VarriableCase (Autodesk Fusion 360 design; units mm, degrees)
Autodesk Fusion 360 part; units mm, degrees
sketch "Sketch1" plane through (0, 0, 0) normal (0, 1, 0) x (1, 0, 0)
  line L0 (140, -74.5) -> (-140, -74.5)
  line L1 (-140, -74.5) -> (-140, 75.5)
  line L2 (-140, 75.5) -> (140, 75.5)
  line L3 (140, 75.5) -> (140, -74.5)
  line L4 (150, -84.5) -> (-150, -84.5)
  line L5 (-150, -84.5) -> (-150, 84.5)
  line L6 (-150, 84.5) -> (150, 84.5)
  line L7 (150, 84.5) -> (150, -84.5)
  line L8 (150, 11.3529) -> (212.0868, 7.5031)
  line L9 (135.5, 63) -> (135.5, -62)
  line L10 (135.5, -62) -> (10.5, -62)
  line L11 (10.5, -62) -> (-9.5, -62)
  line L12 (-9.5, -62) -> (-134.5, -62)
  line L13 (-134.5, -62) -> (-134.5, 63)
  line L14 (-134.5, 63) -> (-9.5, 63)
  line L15 (-9.5, 63) -> (10.5, 63)
  line L16 (10.5, 63) -> (135.5, 63)
  circle A0 centre (-134.5, 63) radius 1.25
  circle A1 centre (-134.5, -62) radius 1.25
  circle A2 centre (-9.5, -62) radius 1.25
  circle A3 centre (-9.5, 63) radius 1.25
  circle A4 centre (10.5, 63) radius 1.25
  circle A5 centre (135.5, 63) radius 1.25
  circle A6 centre (135.5, -62) radius 1.25
  circle A7 centre (-9.5, -62) radius 5
  circle A8 centre (135.5, -62) radius 5
  circle A9 centre (135.5, 63) radius 5
  circle A10 centre (10.5, 63) radius 5
  circle A11 centre (-9.5, 63) radius 5
  circle A12 centre (-134.5, 63) radius 5
  circle A13 centre (-134.5, -62) radius 5
  line L17 (10.5, 63) -> (10.5, -62) construction
  circle A14 centre (10.5, -62) radius 1.25
  circle A15 centre (10.5, -62) radius 5
  dimension "d14" = 2.5
  dimension "d15" = 2.5
  dimension "d16" = 2.5
  dimension "d17" = 2.5
  dimension "d18" = 2.5
  dimension "d19" = 2.5
  dimension "d20" = 2.5
  dimension "d21" = 10
  dimension "d22" = 10
  dimension "d23" = 10
  dimension "d24" = 10
  dimension "d25" = 10
  dimension "d26" = 10
  dimension "d27" = 10
  dimension "d42" = 2.5
  dimension "d43" = 10
  constraint perpendicular L0 L1
  constraint parallel L0 L2
  constraint parallel L1 L3
  constraint horizontal L0
  constraint perpendicular L4 L5
  constraint parallel L4 L6
  constraint parallel L5 L7
  constraint horizontal L4
  constraint coincident L7 L8.start
  constraint perpendicular L9 L10
  constraint parallel L10 L11
  constraint parallel L11 L12
  constraint perpendicular L12 L13
  constraint perpendicular L13 L14
  constraint parallel L14 L15
  constraint perpendicular L9 L16
  constraint coincident L13.end L14.start
  constraint coincident L12.end L13.start
  constraint coincident L11.end L12.start
  constraint coincident L14.end L15.start
  constraint coincident L15.end L16.start
  constraint coincident L9.start L16.end
  constraint coincident L9.end L10.start
  constraint concentric A6 A8
  constraint concentric A5 A9
  constraint concentric A4 A10
  constraint concentric A3 A11
  constraint concentric A0 A12
  constraint concentric A1 A13
  constraint perpendicular L11 L17
  constraint coincident L10.end L11.start
  constraint concentric A14 A15
  measures "d14" diameter of A0
  measures "d15" diameter of A1
  measures "d16" diameter of A2
  measures "d17" diameter of A3
  measures "d18" diameter of A4
  measures "d19" diameter of A5
  measures "d20" diameter of A6
  measures "d21" diameter of A7
  measures "d22" diameter of A8
  measures "d23" diameter of A9
  measures "d24" diameter of A10
  measures "d25" diameter of A11
  measures "d26" diameter of A12
  measures "d27" diameter of A13
  measures "d42" diameter of A14
  measures "d43" diameter of A15
extrude "Extrude1" add sketch "Sketch1" along normal blind 14.28 contours L0 L1 L2 L3 L10 L11 L12 L13 L14 L15 L16 A7 A8 A9 A10 A11 A12 A13 A15 | L3 L9 L10 A6 A8 | L3 A8 | L3 L9 A8 A9 | L9 L10 A6 A8 | L3 L9 L16 A5 A9 | L3 A9 | L10 L11 A14 A15 | L10 L11 A14 A15 | L9 L16 A5 A9 | L11 L12 A2 A7 | L11 L12 A2 A7 | L15 L16 A4 A10 | L15 L16 A4 A10 | L12 L13 A1 A13 | L12 L13 A1 A13 | L14 L15 A3 A11 | L14 L15 A3 A11 | L13 L14 A0 A12 | L13 L14 A0 A12 | L4 L5 L6 L7
chamfer "Chamfer1" distance 5 angle 45 8 edges at (-14.5, 7.14, -63) (-4.5, 7.14, -63) (5.5, 7.14, -63) (15.5, 7.14, -63) (-4.5, 7.14, 62) (-14.5, 7.14, 62) (5.5, 7.14, 62) (15.5, 7.14, 62) tangent chain off
chamfer "Chamfer2" distance 3 angle 45 8 edges at (-129.5, 7.14, -63) (-134.5, 7.14, -58) (-134.5, 7.14, 57) (-129.5, 7.14, 62) (130.5, 7.14, 62) (135.5, 7.14, 57) (135.5, 7.14, -58) (130.5, 7.14, -63) tangent chain off
sketch "Sketch2" plane through (0, 14.28, 0) normal (0, 1, 0) x (-1, 0, 0)
  circle A0 centre (9.5, -63) radius 1.25
  circle A1 centre (134.5, 62) radius 1.25
  circle A2 centre (134.5, -63) radius 1.25
  line L0 (19.5, 62) -> (126.5, 62)
  line L1 (126.5, 62) -> (130.4, 59.1382)
  arc A3 (130.4, 59.1382) -> (131.6382, 57.9) centre (134.5, 62) ccw
  line L2 (131.6382, 57.9) -> (134.5, 54)
  line L3 (134.5, 54) -> (134.5, -55)
  line L4 (134.5, -55) -> (131.6382, -58.9)
  arc A4 (131.6382, -58.9) -> (130.4, -60.1382) centre (134.5, -63) ccw
  line L5 (130.4, -60.1382) -> (126.5, -63)
  line L6 (126.5, -63) -> (19.5, -63)
  line L7 (19.5, -63) -> (12, -58.6699)
  arc A5 (12, -58.6699) -> (7, -58.6699) centre (9.5, -63) ccw
  line L8 (7, -58.6699) -> (-0.5, -63)
  line L9 (-0.5, -63) -> (-8, -58.6699)
  arc A6 (-8, -58.6699) -> (-13, -58.6699) centre (-10.5, -63) ccw
  line L10 (-13, -58.6699) -> (-20.5, -63)
  line L11 (-20.5, -63) -> (-127.5, -63)
  line L12 (-127.5, -63) -> (-131.4, -60.1382)
  arc A7 (-131.4, -60.1382) -> (-132.6382, -58.9) centre (-135.5, -63) ccw
  line L13 (-132.6382, -58.9) -> (-135.5, -55)
  line L14 (-135.5, -55) -> (-135.5, 54)
  line L15 (-135.5, 54) -> (-132.6382, 57.9)
  arc A8 (-132.6382, 57.9) -> (-131.4, 59.1382) centre (-135.5, 62) ccw
  line L16 (-131.4, 59.1382) -> (-127.5, 62)
  line L17 (-127.5, 62) -> (-20.5, 62)
  line L18 (-0.5, 62) -> (7, 57.6699)
  arc A9 (7, 57.6699) -> (12, 57.6699) centre (9.5, 62) ccw
  line L19 (12, 57.6699) -> (19.5, 62)
  circle A10 centre (-135.5, 62) radius 1.25
  circle A11 centre (9.5, 62) radius 1.25
  circle A12 centre (-135.5, -63) radius 1.25
  circle A13 centre (-10.5, -63) radius 1.25
  line L20 (-150, -84.5) -> (150, -84.5)
  line L21 (150, -84.5) -> (150, 84.5)
  line L22 (150, 84.5) -> (-150, 84.5)
  line L23 (-150, 84.5) -> (-150, -84.5)
  circle A14 centre (-135.5, 62) radius 2.5
  circle A15 centre (-135.5, -63) radius 2.5
  circle A16 centre (-10.5, -63) radius 2.5
  circle A17 centre (9.5, -63) radius 2.5
  circle A18 centre (134.5, -63) radius 2.5
  circle A19 centre (134.5, 62) radius 2.5
  circle A20 centre (9.5, 62) radius 2.5
  circle A21 centre (-10.5, 62) radius 1.25
  arc A22 (-13, 57.6699) -> (-8, 57.6699) centre (-10.5, 62) ccw
  line L24 (-20.5, 62) -> (-13, 57.6699)
  line L25 (-8, 57.6699) -> (-0.5, 62)
  circle A23 centre (-10.5, 62) radius 2.5
  dimension "d32" = 5
  dimension "d33" = 5
  dimension "d34" = 5
  dimension "d35" = 5
  dimension "d36" = 5
  dimension "d37" = 5
  dimension "d38" = 5
  dimension "d44" = 5
  constraint concentric A8 A14
  constraint concentric A7 A15
  constraint concentric A6 A16
  constraint concentric A0 A17
  constraint concentric A2 A18
  constraint concentric A1 A19
  constraint concentric A9 A20
  constraint concentric A21 A23
  measures "d32" diameter of A14
  measures "d33" diameter of A15
  measures "d34" diameter of A16
  measures "d35" diameter of A17
  measures "d36" diameter of A18
  measures "d37" diameter of A19
  measures "d38" diameter of A20
  measures "d44" diameter of A23
extrude "Extrude2" cut sketch "Sketch2" against normal blind 7.78 contours A14 | A15 | A16 | A17 | A18 | A19 | A20 | A23
fillet "Fillet1" radius 5 4 edges at (-150, 7.14, 84.5) (-150, 7.14, -84.5) (150, 7.14, 84.5) (150, 7.14, -84.5)
